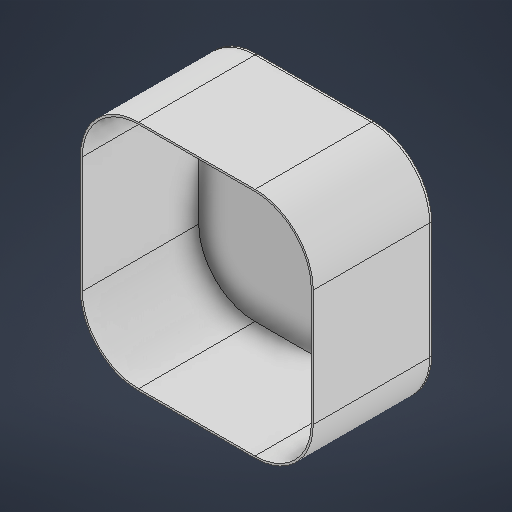
# Autodesk Inventor part: base side cover
Saved by Autodesk Inventor 2025.2 (Build 292293000, 293)
## iProperties
Created: 2024-12-25
Part Number: base side cover
Material: Generic
Document SubType Name: Modeling
Designer: user
Density: 1 g/cm^3
Appearance: Default
Author: user
Autodesk Inventor part; units mm, degrees
ref_plane "YZ Plane" through (0, 0, 0) normal (1, 0, 0) x (0, 1, 0)
ref_plane "XZ Plane" through (0, 0, 0) normal (0, 1, 0) x (-1, 0, 0)
ref_plane "XY Plane" through (0, 0, 0) normal (0, 0, 1) x (1, 0, 0)
sketch "Sketch1" plane through (0, 0, 0) normal (0, 0, 1) x (1, 0, 0)
  circle A0 centre (0, 0) radius 300
  line L0 (150, 300) -> (-150, 300)
  line L1 (-300, 150) -> (-300, -150)
  line L2 (-150, -300) -> (150, -300)
  line L3 (300, -150) -> (300, 150)
  line L4 (300, 300) -> (-300, -300) construction
  line L5 (-300, 300) -> (300, -300) construction
  arc A1 (300, 150) -> (150, 300) centre (150, 150) ccw
  arc A2 (-150, 300) -> (-300, 150) centre (-150, 150) ccw
  arc A3 (-300, -150) -> (-150, -300) centre (-150, -150) ccw
  arc A4 (150, -300) -> (300, -150) centre (150, -150) ccw
  point P0 (300, 0)
  point P1 (0, -300)
  point P2 (-300, 0)
  point P3 (0, 300)
  dimension "d0" = 600
  dimension "d8" = 600
  dimension "d9" = 150
  constraints: 12 end point, 8 point on circle, 8 point on line, 8 tangent, 5 centre point, 3 equal radius, 2 midpoint, 2 parallel, 1 coincident, 1 horizontal, 1 perpendicular
  measures "d0" diameter of A0
  measures "d8" distance of L4.end L5.start
  measures "d9" radius of A1
extrude "Extrusion1" add sketch "Sketch1" along normal blind 5
sketch "Sketch3" plane through (0, 0, 5) normal (0, 0, 1) x (1, 0, 0)
  arc A0 (-150, 300) -> (-300, 150) centre (-150, 150) ccw projected
  line L0 (-300, 150) -> (-300, -150) projected
  line L1 (150, 300) -> (-150, 300) projected
  arc A1 (-150, 300) -> (-300, 150) centre (-150, 150) ccw projected
  line L2 (-300, 150) -> (-300, -150) projected
  arc A2 (-300, -150) -> (-150, -300) centre (-150, -150) ccw projected
  line L3 (-150, -300) -> (150, -300) projected
  arc A3 (150, -300) -> (300, -150) centre (150, -150) ccw projected
  line L4 (300, -150) -> (300, 150) projected
  arc A4 (300, 150) -> (150, 300) centre (150, 150) ccw projected
  line L5 (-150, -300) -> (150, -300) projected
  arc A5 (-150, 295) -> (-295, 150) centre (-150, 150) ccw
  line L6 (-295, 150) -> (-295, -150)
  arc A6 (-295, -150) -> (-150, -295) centre (-150, -150) ccw
  line L7 (-295, -150) -> (-295, 150)
  arc A7 (-150, 295) -> (-295, 150) centre (-150, 150) ccw
  line L8 (-150, 295) -> (150, 295)
  arc A8 (295, 150) -> (150, 295) centre (150, 150) ccw
  line L9 (295, 150) -> (295, -150)
  arc A9 (150, -295) -> (295, -150) centre (150, -150) ccw
  line L10 (-150, -295) -> (150, -295)
  point P0 (0, 0)
  point P1 (-150, 300)
  point P2 (-300, -150)
  point P3 (-150, -295)
  dimension "d10" = 5
  dimension "d11" = 5
  dimension "d12" = 5
  constraints: 10 end point, 10 point on circle, 5 centre point, 1 parallel, 7 other
  measures "d10" radial gap between concentric circles of A0 A5
  measures "d11" radial gap between concentric circles of A2 A6
  measures "d12" distance between parallel lines of L5 L10
extrude "Extrusion3" add sketch "Sketch3" along normal blind 300 separate body
body "Solid1"
body "Solid2"
